DASH_01_calib_abduc_v3 (Autodesk Fusion 360 design; units mm, degrees)
Autodesk Fusion 360 part; units mm, degrees
sketch "Sketch2" plane through (0, 0, 0) normal (1, 0, 0) x (0, 1, 0)
  line L0 (-0.3328, 32.6996) -> (80.4672, 32.6996)
  line L1 (80.4672, 32.6996) -> (80.4672, 27.6996)
  line L2 (80.4672, 27.6996) -> (-0.3328, 27.6996)
  line L3 (-0.3328, 27.6996) -> (-0.3328, 32.6996)
  circle A0 centre (30.9123, -19.2725) radius 45
  line L4 (-0.3328, 27.6996) -> (-0.3328, 17.6996)
  line L5 (-0.3328, 17.6996) -> (80.4672, 17.6996)
  line L6 (80.4672, 17.6996) -> (80.4672, 27.6996)
  dimension "d3" = 80.8
  dimension "d4" = 5
  dimension "d5" = 90
  dimension "d6" = 10
  dimension "d7" = 80.8
  constraint horizontal L0
  constraint vertical L1
  constraint horizontal L2
  constraint vertical L3
  constraint perpendicular L2 L4
  constraint perpendicular L4 L5
  measures "d3" distance of L0.start L0.end
  measures "d4" distance of L0.start L2.end
  measures "d5" diameter of A0
  measures "d6" distance of L2.end L4.end
  measures "d7" distance of L4.end L5.end
extrude "Extrude1" add sketch "Sketch2" along normal blind 60 contours L0 L1 L2 L3 | L2 A0 L4 L5 L6
fillet "Fillet1" radius 20 1 edges at (30, 56.5651, 17.6996)
fillet "Fillet2" radius 7.5 1 edges at (30, 5.2595, 17.6996)
fillet "Fillet3" radius 2.5 2 edges at (30, -0.3328, 17.6996) (30, 80.4672, 17.6996)
move_face "OffsetFaces1" offset 4 1 faces at (20, 26.6005, 32.6996)
